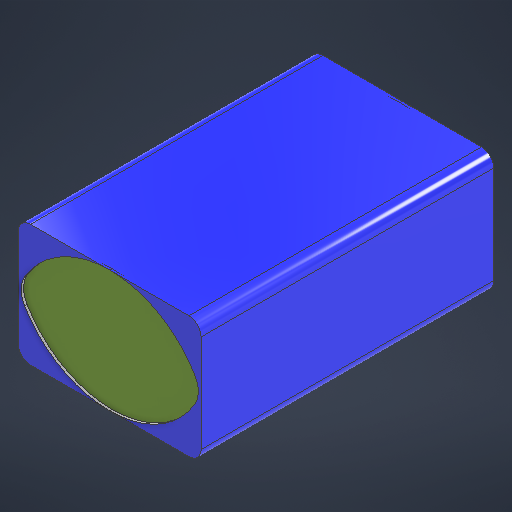
# Autodesk Inventor part: Khối pin sạc Li-ion 12V 21Ah 30A 3S MTM
Saved by Autodesk Inventor 2026.2 (Build 302298000, 298)
## iProperties
Created: 2026-06-12
Part Number: Khối pin sạc Li-ion 12V 21Ah 30A 3S MTM
Material: Generic
Document SubType Name: Modeling
Designer: thita
Density: 1 g/cm^3
Appearance: Default
Author: thita
Autodesk Inventor part; units mm, degrees
ref_plane "YZ Plane" through (0, 0, 0) normal (1, 0, 0) x (0, 1, 0)
ref_plane "XZ Plane" through (0, 0, 0) normal (0, 1, 0) x (-1, 0, 0)
ref_plane "XY Plane" through (0, 0, 0) normal (0, 0, 1) x (1, 0, 0)
sketch "Sketch1" plane through (0, 0, 0) normal (0, 1, 0) x (-1, 0, 0)
  line L0 (-37.5, 60) -> (-37.5, -60)
  line L1 (-37.5, -60) -> (37.5, -60)
  line L2 (37.5, -60) -> (37.5, 60)
  line L3 (37.5, 60) -> (-37.5, 60)
  line L4 (-37.5, 60) -> (37.5, -60) construction
  line L5 (-37.5, -60) -> (37.5, 60) construction
  point P0 (0, 0)
  dimension "d0" = 120
  dimension "d1" = 75
  constraints: 12 end point, 2 midpoint, 2 parallel, 1 perpendicular, 1 vertical
  measures "d0" distance of L0.start L0.end
  measures "d1" distance of L1.end L0.end
extrude "Extrusion1" add sketch "Sketch1" along normal blind 50
fillet "Fillet1" radius 5 4 edges at (-37.5, 50, 0) (-37.5, 0, 0) (37.5, 0, 0) (37.5, 50, 0)
sketch "Sketch2" plane through (32.5, 0, -60) normal (0, 0, -1) x (-1, 0, 0)
  arc A0 (0, 50) -> (-5, 45) centre (0, 45) ccw projected
  line L0 (-5, 5) -> (-5, 45) projected
  arc A1 (-5, 5) -> (0, 0) centre (0, 5) ccw projected
  line L1 (0, 0) -> (65, 0) projected
  arc A2 (65, 0) -> (70, 5) centre (65, 5) ccw projected
  line L2 (70, 5) -> (70, 45) projected
  arc A3 (70, 45) -> (65, 50) centre (65, 45) ccw projected
  line L3 (0, 50) -> (65, 50) projected
  line L4 (70, 5) -> (70, 45) projected
  arc A4 (67.4397, 30.102) -> (-2.4397, 30.102) centre (32.5, 9.375) ccw
  arc A5 (-2.4397, 19.898) -> (67.4397, 19.898) centre (32.5, 40.625) ccw
  arc A6 (67.4397, 19.898) -> (67.4397, 30.102) centre (58.8391, 25) ccw
  arc A7 (-2.4397, 30.102) -> (-2.4397, 19.898) centre (6.1609, 25) ccw
  point P0 (32.5, 0)
  dimension "d5" = 10
  constraints: 9 point on circle, 4 centre point, 4 tangent, 1 equal radius
  measures "d5" radius of A6
extrude "Extrusion2" cut sketch "Sketch2" against normal blind 1 contours A4 A6 A5 A7
mirror "Mirror1" about plane through (0, 0, 0) normal (0, 0, 1) of "Extrusion2"
body "Solid1"
